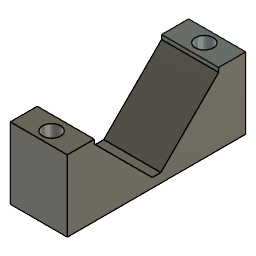
Main Bottom Side Assembly (Autodesk Fusion 360 archive; units mm, degrees)
design "Drive Motor Mount Base Top Half"
Autodesk Fusion 360 part; units mm, degrees
(part 1 of 3)
ref_plane "WorkPlane1" through (0, 0, 0) normal (1, 0, 0) x (0, 1, 0)
sketch "Sketch3" plane through (0, 0, 0) normal (1, 0, 0) x (0, 1, 0)
  line L0 (-15.875, 0) -> (15.875, 0)
  line L1 (15.875, 0) -> (15.875, -12.7)
  line L2 (15.875, -12.7) -> (-15.875, -12.7)
  line L3 (-15.875, -12.7) -> (-15.875, 0)
  line L4 (-11.049, 0) -> (-11.049, -0.762)
  line L5 (-11.049, -0.762) -> (-0.762, -11.049)
  line L6 (-0.762, -11.049) -> (0.762, -11.049)
  line L7 (0.762, -11.049) -> (11.049, -0.762)
  line L8 (11.049, -0.762) -> (11.049, 0)
  dimension "d12" = 31.75
  dimension "d13" = 12.7
  dimension "d14" = 0.762
  dimension "d15" = 4.826
  dimension "d16" = 4.826
  dimension "d17" = 1.524
  constraint horizontal L0
  constraint vertical L1
  constraint horizontal L2
  constraint vertical L3
  constraint coincident L0 L4.start
  constraint perpendicular L0 L4
  constraint horizontal L6
  constraint coincident L0 L8.end
  constraint perpendicular L0 L8
  constraint equal L4 L8
  constraint equal L5 L7
  constraint perpendicular L5 L7
  constraint midpoint origin L0
  measures "d12" distance of L1.end L2.end
  measures "d13" distance of L0.start L2.end
  measures "d14" distance of L4.start L4.end
  measures "d15" distance of L0.start L4.start
  measures "d16" distance of L0.end L8.end
  measures "d17" distance of L5.end L6.end
extrude "Extrude2" add sketch "Sketch3" along normal blind 10.16 contours L0 L1 L2 L3 L4 L5 L6 L7 L8
sketch "Sketch4" plane through (0, 0, 0) normal (0, 0, 1) x (-1, 0, 0)
  line L0 (0, -15.875) -> (0, -11.049)
  line L1 (0, -11.049) -> (-10.16, -11.049)
  line L2 (-10.16, -11.049) -> (-10.16, -15.875)
  line L3 (-10.16, -15.875) -> (0, -15.875)
sketch "Sketch5" plane through (10.16, 0, 0) normal (1, 0, 0) x (0, -1, 0)
  line L0 (-11.049, 0.762) -> (-0.762, 11.049)
  line L1 (-0.762, 11.049) -> (0.762, 11.049)
  line L2 (0.762, 11.049) -> (11.049, 0.762)
  line L3 (11.049, 0.762) -> (11.049, 0)
  line L4 (11.049, 0) -> (15.875, 0)
  line L5 (15.875, 0) -> (15.875, 12.7)
  line L6 (15.875, 12.7) -> (-15.875, 12.7)
  line L7 (-15.875, 12.7) -> (-15.875, 0)
  line L8 (-15.875, 0) -> (-11.049, 0)
  line L9 (-11.049, 0) -> (-11.049, 0.762)
  arc A0 (-12.7, 0) -> (12.7, 0) centre (0, 0) ccw
  line L10 (-11.6397, -5.08) -> (15.875, -5.08)
  line L11 (11.6397, -5.08) -> (-15.875, -5.08)
  line L12 (-15.875, 0) -> (-11.049, 0)
  dimension "d21" = 5.08
  dimension "d22" = 5.08
  dimension "d34" = 12.7
  constraint coincident A0.centre origin
  constraint coincident L8 A0.end
  constraint coincident L4 A0.start
  constraint coincident A0 L10.start
  constraint coincident L5 L10.end
  constraint perpendicular L5 L10
  constraint coincident A0 L11.start
  constraint coincident L7 L11.end
  constraint perpendicular L7 L11
  measures "d21" distance of L4 L10
  measures "d22" distance of L11 L12
  measures "d34" radius of A0
extrude "Extrude3" add sketch "Sketch5" against normal up to surface (10.16 mm away) contours L0 L1 L2 L3 L4 L5 L6 L7 L8 L9 L12
sketch "Sketch7" plane through (0, 0, 0) normal (0, 0, 1) x (-1, 0, 0)
  line L0 (0, 11.049) -> (0, 15.875)
  line L1 (0, 15.875) -> (-10.16, 15.875)
  line L2 (-10.16, 15.875) -> (-10.16, 11.049)
  line L3 (-10.16, 11.049) -> (0, 11.049)
  circle A0 centre (-5.08, 13.589) radius 1.6
  circle A1 centre (-5.08, -13.589) radius 1.6
  line L4 (-10.16, -15.875) -> (0, -15.875)
  line L5 (-10.16, -11.049) -> (-10.16, -15.875)
  dimension "d35" = 3.2
  dimension "d36" = 3.2
  dimension "d37" = 2.286
  dimension "d38" = 2.286
  dimension "d39" = 5.08
  dimension "d40" = 5.08
  measures "d35" diameter of A1
  measures "d36" diameter of A0
  measures "d37" distance of A1.centre L4
  measures "d38" distance of L1 A0.centre
  measures "d39" distance of L2 A0.centre
  measures "d40" distance of A1.centre L5
extrude "Extrude5" cut sketch "Sketch7" against normal blind 12.7 contours A0 | A1

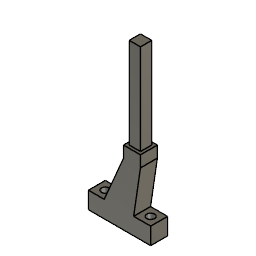
design "Rear Frame Mount"
Autodesk Fusion 360 part; units mm, degrees
sketch "Sketch1" plane through (0, 0, 0) normal (0, 1, 0) x (1, 0, 0)
  line L0 (0, 0) -> (-25.4, 0)
  line L1 (-25.4, 0) -> (-25.4, -9.525)
  line L2 (-25.4, -9.525) -> (0, -9.525)
  line L3 (0, -9.525) -> (0, 0)
  line L4 (-25.4, 0) -> (-34.925, 0)
  line L5 (-34.925, 0) -> (-34.925, -9.525)
  line L6 (-34.925, -9.525) -> (-25.4, -9.525)
  line L7 (-25.4, -9.525) -> (-25.4, 0)
  line L8 (-26.035, -9.525) -> (-15.24, -34.925)
  line L9 (-15.24, -34.925) -> (-5.715, -34.925)
  line L10 (-5.715, -34.925) -> (-9.525, -9.525)
  line L11 (-15.24, -34.925) -> (-5.715, -34.925)
  line L12 (-5.715, -34.925) -> (-5.715, -41.275)
  line L13 (-5.715, -41.275) -> (-15.24, -41.275)
  line L14 (-15.24, -41.275) -> (-15.24, -34.925)
  dimension "d3" = 34.925
  dimension "d4" = 9.525
  dimension "d5" = 25.4
  dimension "d6" = 9.525
  dimension "d7" = 9.525
  dimension "d26" = 6.35
  dimension "d27" = 25.4
  dimension "d28" = 9.525
  dimension "d30" = 16.51
  dimension "d31" = 3.81
  dimension "d32" = 9.525
  constraint horizontal L0
  constraint vertical L1
  constraint horizontal L2
  constraint vertical L3
  constraint coincident L0.start L3.end
  constraint horizontal L4
  constraint vertical L5
  constraint horizontal L6
  constraint vertical L7
  constraint coincident L2 L8.start
  constraint perpendicular L1 L9
  constraint coincident L2 L10.end
  constraint horizontal L11
  constraint vertical L12
  constraint horizontal L13
  constraint vertical L14
  constraint horizontal L0.end L4.end
  measures "d3" distance of L3 L5
  measures "d4" distance of L0.end L4.end
  measures "d5" distance of L0.start L0.end
  measures "d6" distance of L4.end L5.end
  measures "d7" distance of L0.start L2.end
  measures "d26" distance of L9.end L12.end
  measures "d27" distance of L2 L9
  measures "d28" distance of L12 L14
  measures "d30" distance of L8.start L10.end
  measures "d31" horizontal distance of L10.end L9.end
  measures "d32" distance of L2.end L10.end
extrude "Extrude1" add sketch "Sketch1" along normal blind 9.525
sketch "Sketch2" plane through (0, 0, 9.525) normal (0, 0, 1) x (-1, 0, 0)
  line L0 (34.925, 0) -> (26.035, 0)
  line L1 (0, 0) -> (0, -9.525)
  line L2 (26.035, -9.525) -> (34.925, -9.525)
  line L3 (34.925, -9.525) -> (34.925, 0)
  circle A0 centre (30.1625, -4.7625) radius 2.1971
  circle A1 centre (4.7625, -4.7625) radius 2.1971
  line L4 (26.035, 0) -> (26.035, -9.525)
  line L5 (9.525, 0) -> (0, 0)
  line L6 (0, -9.525) -> (9.525, -9.525)
  line L7 (9.525, -9.525) -> (9.525, 0)
  dimension "d10" = 4.3942
  dimension "d11" = 4.3942
  dimension "d12" = 4.7625
  dimension "d13" = 4.7625
  dimension "d14" = 25.4
  dimension "d15" = 4.7625
  measures "d10" diameter of A0
  measures "d11" diameter of A1
  measures "d12" distance of L2 A0.centre
  measures "d13" distance of L2 A1.centre
  measures "d14" distance of A0.centre A1.centre
  measures "d15" distance of L3 A0.centre
extrude "Extrude2" cut sketch "Sketch2" against normal blind 9.525 contours A0 | A1
sketch "Sketch5" plane through (0, 0, 41.275) normal (0, 0, 1) x (-1, 0, 0)
  line L0 (15.24, 0) -> (5.715, 0)
  line L1 (5.715, 0) -> (5.715, -9.525)
  line L2 (5.715, -9.525) -> (15.24, -9.525)
  line L3 (15.24, -9.525) -> (15.24, 0)
  line L4 (13.6525, -7.9375) -> (7.3025, -7.9375)
  line L5 (7.3025, -7.9375) -> (7.3025, -1.5875)
  line L6 (7.3025, -1.5875) -> (13.6525, -1.5875)
  line L7 (13.6525, -1.5875) -> (13.6525, -7.9375)
  dimension "d33" = 6.35
  dimension "d34" = 6.35
  dimension "d35" = 1.5875
  dimension "d36" = 1.5875
  constraint horizontal L4
  constraint vertical L5
  constraint horizontal L6
  constraint vertical L7
  measures "d33" distance of L4.end L5.end
  measures "d34" distance of L4.start L4.end
  measures "d35" distance of L2 L4
  measures "d36" distance of L1 L5
extrude "Extrude5" add sketch "Sketch5" along normal blind 50.8 contours L4 L5 L6 L7
equation "d12 = ( 0.375 / 2 ) * 1 in"
equation "d13 = ( 3 / 16 ) * 1 in"
equation "d15 = ( 3 / 16 ) * 1 in"
equation "d28 = ( 3 / 8 ) * 1 in"
equation "d35 = ( 1 / 16 ) * 1 in"
equation "d36 = ( 1 / 16 ) * 1 in"
equation "d29 = ( 3 / 8 ) * 1 in"

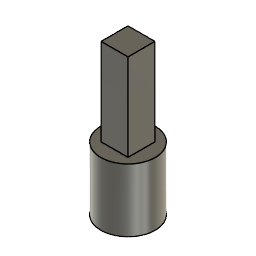
design "Small bevel coupling"
Autodesk Fusion 360 part; units mm, degrees
sketch "Sketch1" plane through (0, 0, 0) normal (0, 0, 1) x (1, 0, 0)
  line L0 (-1.397, 1.6995) -> (1.397, 1.6995)
  arc A0 (-1.397, 1.6995) -> (1.397, 1.6995) centre (0, 0) ccw
  circle A1 centre (0, 0) radius 3.175
  dimension "d1" = 4.4
  dimension "d2" = 2.794
  dimension "d8" = 3.175
  constraint coincident A0.centre A1.centre
  constraint horizontal L0
  constraint concentric A0 A1
  measures "d1" diameter of A0
  measures "d2" distance of L0.start L0.end
  measures "d8" radius of A1
extrude "Extrude1" add sketch "Sketch1" along normal blind 6.35
sketch "Sketch4" plane through (0, 0, 6.35) normal (0, 0, 1) x (-1, 0, 0)
  arc A0 (1.397, -1.6995) -> (-1.397, -1.6995) centre (0, 0) ccw
  line L0 (1.397, -1.6995) -> (-1.397, -1.6995)
  circle A1 centre (0, 0) radius 3.175
  circle A2 centre (0, 0) radius 3.175
  dimension "d9" = 6.35
  constraint coincident A0.centre A1.centre
  measures "d9" diameter of A2
extrude "Extrude2" add sketch "Sketch4" along normal blind 1.016 contours A0 L0 | A1 A2
sketch "Sketch5" plane through (0, 0, 7.366) normal (0, 0, 1) x (-1, 0, 0)
  circle A0 centre (0, 0) radius 3.175
  line L0 (-1.5748, -1.5748) -> (1.5748, -1.5748)
  line L1 (1.5748, -1.5748) -> (1.5748, 1.5748)
  line L2 (1.5748, 1.5748) -> (-1.5748, 1.5748)
  line L3 (-1.5748, 1.5748) -> (-1.5748, -1.5748)
  line L4 (-1.5748, -1.5748) -> (1.5748, 1.5748) construction
  line L5 (1.5748, -1.5748) -> (-1.5748, 1.5748) construction
  dimension "d12" = 3.1496
  dimension "d13" = 3.1496
  constraint horizontal L0
  constraint perpendicular L0 L1
  constraint parallel L0 L2
  constraint parallel L1 L3
  constraint coincident L4 A0.centre
  constraint coincident L5 A0.centre
  constraint coincident A0.centre origin
  measures "d12" distance of L0.end L1.end
  measures "d13" distance of L0.start L0.end
extrude "Extrude3" add sketch "Sketch5" along normal blind 10.16 contours L0 L1 L2 L3

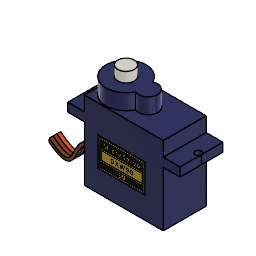
design "Servo-Motor"
Autodesk Fusion 360 part; units mm, degrees
sketch "Sketch1" plane through (0, 0, 0) normal (0, -1, 0) x (1, 0, 0)
  line L0 (-16.065, 4.55) -> (-11.275, 4.55)
  line L1 (-11.275, 4.55) -> (-11.275, -11.2)
  line L2 (-11.275, -11.2) -> (11.275, -11.2)
  line L3 (11.275, -11.2) -> (11.275, 4.55)
  line L4 (11.275, 4.55) -> (16.065, 4.55)
  line L5 (16.065, 4.55) -> (16.065, 7.05)
  line L6 (16.065, 7.05) -> (11.275, 7.05)
  line L7 (11.275, 7.05) -> (11.275, 11.2)
  line L8 (11.275, 11.2) -> (-11.275, 11.2)
  line L9 (-11.275, 11.2) -> (-11.275, 7.05)
  line L10 (-11.275, 7.05) -> (-16.065, 7.05)
  line L11 (-16.065, 7.05) -> (-16.065, 4.55)
  line L12 (-11.275, 11.2) -> (11.275, 11.2)
  line L13 (11.275, 11.2) -> (11.275, 7.05)
  line L14 (11.275, 7.05) -> (16.065, 7.05)
  line L15 (16.065, 4.55) -> (16.065, 7.05)
  line L16 (16.065, 4.55) -> (11.275, 4.55)
  line L17 (11.275, 4.55) -> (11.275, -11.2)
  line L18 (11.275, -11.2) -> (-11.275, -11.2)
  line L19 (-11.275, -11.2) -> (-11.275, 4.55)
  line L20 (-16.065, 4.55) -> (-16.065, 7.05)
  line L21 (-16.065, 7.05) -> (-11.275, 7.05)
  line L22 (-11.275, 7.05) -> (-11.275, 11.2)
  line L23 (-11.275, 4.55) -> (-16.065, 4.55)
  constraint coincident L8.end L9.start
  constraint coincident L7.end L8.start
  constraint coincident L6.end L7.start
  constraint coincident L5.end L6.start
  constraint coincident L4.end L5.start
  constraint coincident L3.end L4.start
  constraint coincident L2.end L3.start
  constraint coincident L1.end L2.start
  constraint coincident L0.end L1.start
  constraint coincident L0.start L11.end
  constraint coincident L10.end L11.start
  constraint coincident L9.end L10.start
extrude "Extrude1" add sketch "Sketch1" along normal blind 12.3 makes body 1
move_body "Move1" bodies 1 to x (1, 0, 0) y (0, 1, 0) z (0, 0, 1) at (0, 6.15, 0)
sketch "Sketch2" plane through (0, 0, 11.2) normal (0, 0, 1) x (-1, 0, 0)
  line L0 (-11.275, -6.15) -> (11.275, -6.15)
  line L1 (11.275, -6.15) -> (11.275, 6.15)
  line L2 (11.275, 6.15) -> (-11.275, 6.15)
  line L3 (-11.275, 6.15) -> (-11.275, -6.15)
  line L4 (16.065, -6.15) -> (16.065, 6.15)
  line L5 (-16.065, -6.15) -> (-16.065, 6.15)
  line L6 (16.065, 0) -> (-16.065, 0) construction
  line L7 (0, 6.15) -> (0, -6) construction
  circle A0 centre (15.19, 0) radius 0.875
  circle A1 centre (-15.19, 0) radius 0.875
  line L8 (-11.275, 0) -> (-3.525, 0) construction
  line L9 (-3.525, 3.3214) -> (-3.525, -3) construction
  arc A2 (0.3298, 2.4642) -> (0.3298, -2.4642) centre (-0.81, 0) ccw
  arc A3 (0.3298, -2.4642) -> (0.3298, 2.4642) centre (5.525, 0) ccw
  dimension "d10" = 1.75
  dimension "d11" = 11.5
  dimension "d12" = 7.75
  dimension "d13" = 5.43
  constraint midpoint L5 L6.end
  constraint midpoint L2 L7.start
  constraint perpendicular L6 L7
  constraint coincident L6 A0.centre
  constraint tangent L4 A0
  constraint symmetric L7 A0 A1
  constraint coincident L6 A3.centre
  constraint tangent L1 A3
  constraint midpoint L3 L8.start
  constraint horizontal L8
  constraint coincident L6 A2.centre
  constraint perpendicular L6 L9
  constraint tangent L9 A2
  measures "d10" diameter of A0
  measures "d11" diameter of A3
  measures "d12" distance of L8.start L8.end
  measures "d13" diameter of A2
extrude "Extrude2" add sketch "Sketch2" along normal blind 4.45 contours A2 A3 bodies 1
copy_body "Body->Comp1" bodies 1 removing the originals makes body 2 in component "Blue Body"
sketch "Sketch1 (2)" plane through (0, 0, 15.65) normal (0, 0, 1) x (-1, 0, 0) in component "Gears"
  arc A0 (0.3298, -2.4642) -> (0.3298, 2.4642) centre (5.525, 0) ccw
  arc A1 (0.3298, 2.4642) -> (0.3298, -2.4642) centre (-0.81, 0) ccw
  circle A2 centre (5.525, 0) radius 2.35
  dimension "d16" = 4.7
  constraint concentric A0 A2
  measures "d16" diameter of A2
extrude "Extrude1'" add sketch "Sketch1 (2)" along normal blind 2.88 separate body contours A2 makes body 3 in component "Gears"
extrude "Extrude1''" cut sketch "Sketch2" against normal blind 2.5 from surface at -4.15 contours A0 | A1 bodies 2 in component "Blue Body"
sketch "Sketch1 (3)" plane through (-11.275, 0, 0) normal (-1, 0, 0) x (0, -1, 0) in component "Wires"
  line L0 (-6.15, 4.55) -> (-6.15, -11.2)
  line L1 (-6.15, -11.2) -> (6.15, -11.2)
  line L2 (6.15, -11.2) -> (6.15, 4.55)
  line L3 (6.15, 4.55) -> (-6.15, 4.55)
  line L4 (0, -11.2) -> (0, -6.45) construction
  line L5 (1.65, -6.45) -> (1.65, -5.45)
  line L6 (1.65, -5.45) -> (-1.65, -5.45)
  line L7 (-1.65, -5.45) -> (-1.65, -6.45)
  line L8 (-1.65, -6.45) -> (1.65, -6.45)
  line L9 (-1.65, -5.45) -> (-0.55, -5.45)
  line L10 (-0.55, -5.45) -> (0.55, -5.45)
  line L11 (0.55, -5.45) -> (0.55, -6.45)
  line L12 (-0.55, -5.45) -> (-0.55, -6.45)
  dimension "d35" = 1.65
  dimension "d36" = 1
  dimension "d37" = 3.3
  dimension "d38" = 1.1
  dimension "d39" = 1.1
  constraint midpoint L1 L4.start
  constraint vertical L4
  constraint vertical L5
  constraint horizontal L6
  constraint vertical L7
  constraint perpendicular L5 L8
  constraint horizontal L9
  constraint horizontal L10
  constraint coincident L8 L11.end
  constraint perpendicular L8 L11
  constraint coincident L8 L12.end
  constraint perpendicular L8 L12
  measures "d35" distance of L4.end L7.end
  measures "d36" distance of L7.end L6.end
  measures "d37" distance of L7.end L5.start
  measures "d38" distance of L6.end L9.end
  measures "d39" distance of L9.end L10.end
sketch "Sketch2 (2)" plane through (0, 0, 0) normal (0, 1, 0) x (1, 0, 0) in component "Wires"
  spline S0 degree 5 poles (-11.275, 6.45) (-11.5653, 6.2839) (-12.1299, 5.9875) (-12.9291, 5.6496) (-13.8988, 5.4144) (-14.9497, 5.4819) (-15.8436, 5.9016) (-16.5945, 6.6425) (-17.233, 7.6365) (-17.8087, 8.7735) (-18.38, 9.9234) (-19.0073, 10.9519) (-19.7452, 11.7374) (-20.6338, 12.1904) (-21.694, 12.2646) (-22.9344, 11.9406) (-24.0716, 11.3613) (-25.0048, 10.7492) (-25.6623, 10.2628) (-26, 10) knots 0 0 0 0 0 0 0.066667 0.133333 0.2 0.266667 0.333333 0.4 0.466667 0.533333 0.6 0.666667 0.733333 0.8 0.866667 0.933333 1 1 1 1 1 1
  point P0 (-16.3437, 6.45)
  point P1 (-19.5666, 11.4764)
  point P2 (-11.275, 6.45)
  constraint coincident P2 S0.start
sweep "Sweep1" add profiles "Sketch1 (3)" path "Sketch2 (2)" along S0 section 1 contours L6 L7 L8 L9 L12 separate body makes body 4 in component "Wires"
sweep "Sweep2" add profiles "Sketch1 (3)" path "Sketch2 (2)" along S0 section 1 contours L6 L8 L10 L11 L12 separate body makes body 5 in component "Wires"
sweep "Sweep3" add profiles "Sketch1 (3)" path "Sketch2 (2)" along S0 section 1 contours L5 L6 L8 L11 separate body makes body 6 in component "Wires"
component "Gears" placed x (1, 0, 0) y (0, 1, 0) z (0, 0, 1) at (0, 0, 0)
component "Blue Body" placed x (1, 0, 0) y (0, 1, 0) z (0, 0, 1) at (0, 0, 0)
component "Wires" placed x (1, 0, 0) y (0, 1, 0) z (0, 0, 1) at (0, 0, 0)
equation "d35 = ( 3.3 / 2 ) * 1 mm"
equation "d38 = ( 3.3 / 3 ) * 1 mm"
equation "d39 = ( 3.3 / 3 ) * 1 mm"
named bodies: "Orange", "Red", "Brown"

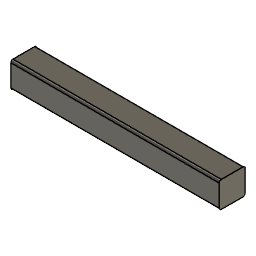
design "Front steering axle"
Autodesk Fusion 360 part; units mm, degrees
sketch "Sketch1" plane through (0, 0, 0) normal (1, 0, 0) x (0, 1, 0)
  line L0 (0, 3.175) -> (3.175, 3.175)
  line L1 (3.175, 3.175) -> (3.175, 0)
  line L2 (3.175, 0) -> (0, 0)
  line L3 (0, 0) -> (0, 3.175)
  dimension "d1" = 3.175
  dimension "d2" = 3.175
  constraint horizontal L0
  constraint vertical L1
  constraint horizontal L2
  constraint vertical L3
  constraint coincident L2.end L3.start
  measures "d1" distance of L0.end L1.end
  measures "d2" distance of L0.start L0.end
extrude "Extrude1" add sketch "Sketch1" along normal blind 25.4
fillet "Fillet1" radius 0.254 4 edges at (12.7, 0, 3.175) (12.7, 3.175, 3.175) (12.7, 0, 0) (12.7, 3.175, 0)

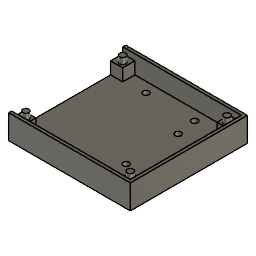
design "Controller Mounting"
Autodesk Fusion 360 part; units mm, degrees
sketch "Sketch1" plane through (0, 0, 0) normal (0, 0, 1) x (1, 0, 0)
  line L0 (0, 0) -> (65.175, 0)
  line L1 (65.175, 0) -> (65.175, 61.175)
  line L2 (65.175, 61.175) -> (0, 61.175)
  line L3 (0, 61.175) -> (0, 0)
  dimension "d1" = 61.175
  dimension "d2" = 65.175
  constraint horizontal L0
  constraint vertical L1
  constraint horizontal L2
  constraint vertical L3
  constraint coincident L0.start L3.end
  measures "d1" distance of L0.start L2.end
  measures "d2" distance of L0.start L0.end
extrude "Extrude1" add sketch "Sketch1" along normal blind 12.7
sketch "Sketch4" plane through (0, 0, 12.7) normal (0, 0, 1) x (-1, 0, 0)
  line L0 (0, -61.175) -> (0, 0)
  line L1 (0, 0) -> (-65.175, 0)
  line L2 (-65.175, 0) -> (-65.175, -61.175)
  line L3 (-65.175, -61.175) -> (0, -61.175)
  line L4 (-1.5875, -1.5875) -> (-63.5875, -1.5875)
  line L5 (-63.5875, -1.5875) -> (-63.5875, -59.5875)
  line L6 (-63.5875, -59.5875) -> (-1.5875, -59.5875)
  line L7 (-1.5875, -59.5875) -> (-1.5875, -1.5875)
  dimension "d10" = 1.5875
  dimension "d11" = 1.5875
  dimension "d12" = 1.5875
  dimension "d13" = 1.5875
  constraint horizontal L4
  constraint vertical L5
  constraint horizontal L6
  constraint vertical L7
  measures "d10" distance of L0 L7
  measures "d11" distance of L3 L6
  measures "d12" distance of L1 L4
  measures "d13" distance of L2 L5
extrude "Extrude2" cut sketch "Sketch4" against normal blind 9.525 contours L4 L5 L6 L7
sketch "Sketch5" plane through (0, 0, 0) normal (-1, 0, 0) x (0, -1, 0)
  line L0 (-61.175, 0) -> (0, 0)
  line L1 (0, 0) -> (0, 12.7)
  line L2 (0, 12.7) -> (-61.175, 12.7)
  line L3 (-61.175, 12.7) -> (-61.175, 0)
  line L4 (-53.2375, 12.7) -> (-7.9375, 12.7)
  line L5 (-7.9375, 12.7) -> (-7.9375, 0)
  line L6 (-53.2375, 0) -> (-53.2375, 12.7)
  line L7 (-53.2375, 3.175) -> (-59.5875, 3.175)
  line L8 (-59.5875, 3.175) -> (-59.5875, 12.7)
  line L9 (-59.5875, 12.7) -> (-53.2375, 12.7)
  line L10 (-53.2375, 12.7) -> (-53.2375, 3.175)
  line L11 (-7.9375, 3.175) -> (-1.5875, 3.175)
  line L12 (-1.5875, 3.175) -> (-1.5875, 12.7)
  line L13 (-1.5875, 12.7) -> (-7.9375, 12.7)
  line L14 (-7.9375, 12.7) -> (-7.9375, 3.175)
  line L15 (-53.2375, 3.175) -> (-7.9375, 3.175)
  dimension "d76" = 1.5875
  dimension "d77" = 3.175
  dimension "d78" = 3.175
  dimension "d79" = 1.5875
  dimension "d80" = 6.35
  dimension "d81" = 6.35
  constraint horizontal L4
  constraint vertical L5
  constraint vertical L6
  constraint coincident L2 L4.start
  constraint horizontal L5.end L6.start
  constraint horizontal L0.end L6.start
  constraint horizontal L7
  constraint vertical L8
  constraint horizontal L9
  constraint vertical L10
  constraint coincident L2 L8.end
  constraint coincident L6 L7.start
  constraint horizontal L11
  constraint vertical L12
  constraint horizontal L13
  constraint vertical L14
  constraint coincident L2 L12.end
  constraint coincident L5 L11.start
  measures "d76" distance of L3 L8
  measures "d77" distance of L0 L7
  measures "d78" distance of L0 L11
  measures "d79" distance of L1 L12
  measures "d80" distance of L8 L10
  measures "d81" distance of L12 L14
extrude "Extrude3" cut sketch "Sketch5" against normal blind 1.5875
sketch "Sketch6" plane through (0, 0, 3.175) normal (0, 0, 1) x (-1, 0, 0)
  circle A0 centre (-59.8375, -5.3375) radius 1.65
  circle A1 centre (-5.3375, -5.3375) radius 1.65
  circle A2 centre (-59.8375, -55.8375) radius 1.65
  circle A3 centre (-5.3375, -55.8375) radius 1.65
  line L0 (-63.5875, -1.5875) -> (-57.2375, -1.5875)
  line L1 (-57.2375, -1.5875) -> (-57.2375, -7.9375)
  line L2 (-57.2375, -7.9375) -> (-63.5875, -7.9375)
  line L3 (-63.5875, -7.9375) -> (-63.5875, -1.5875)
  line L4 (-63.5875, -59.5875) -> (-57.2375, -59.5875)
  line L5 (-57.2375, -59.5875) -> (-57.2375, -53.2375)
  line L6 (-57.2375, -53.2375) -> (-63.5875, -53.2375)
  line L7 (-63.5875, -53.2375) -> (-63.5875, -59.5875)
  line L8 (-1.5875, -59.5875) -> (-7.9375, -59.5875)
  line L9 (-7.9375, -59.5875) -> (-7.9375, -53.2375)
  line L10 (-7.9375, -53.2375) -> (-1.5875, -53.2375)
  line L11 (-1.5875, -53.2375) -> (-1.5875, -59.5875)
  line L12 (-1.5875, -1.5875) -> (-7.9375, -1.5875)
  line L13 (-7.9375, -1.5875) -> (-7.9375, -7.9375)
  line L14 (-7.9375, -7.9375) -> (-1.5875, -7.9375)
  line L15 (-1.5875, -7.9375) -> (-1.5875, -1.5875)
  line L16 (-65.175, 0) -> (-65.175, -61.175)
  line L17 (-65.175, -61.175) -> (0, -61.175)
  line L18 (-1.5875, -1.5875) -> (-63.5875, -1.5875)
  line L19 (-63.5875, -1.5875) -> (-63.5875, -59.5875)
  line L20 (-63.5875, -59.5875) -> (-1.5875, -59.5875)
  line L21 (-1.5875, -59.5875) -> (-1.5875, -1.5875)
  dimension "d82" = 3.3
  dimension "d83" = 50.5
  dimension "d84" = 50.5
  dimension "d85" = 54.5
  dimension "d86" = 3.3
  dimension "d87" = 3.3
  dimension "d88" = 5.3375
  dimension "d89" = 5.3375
  dimension "d90" = 6.35
  dimension "d91" = 6.35
  dimension "d92" = 6.35
  dimension "d93" = 6.35
  dimension "d94" = 6.35
  dimension "d95" = 6.35
  dimension "d96" = 6.35
  dimension "d97" = 6.35
  dimension "d98" = 1.5875
  dimension "d100" = 1.5875
  dimension "d101" = 1.5875
  dimension "d102" = 1.5875
  constraint horizontal A0.centre A1.centre
  constraint horizontal A2.centre A3.centre
  constraint vertical A1.centre A3.centre
  constraint equal A0 A1
  constraint horizontal L0
  constraint vertical L1
  constraint horizontal L2
  constraint vertical L3
  constraint horizontal L4
  constraint vertical L5
  constraint horizontal L6
  constraint vertical L7
  constraint horizontal L8
  constraint vertical L9
  constraint horizontal L10
  constraint vertical L11
  constraint horizontal L12
  constraint vertical L13
  constraint horizontal L14
  constraint vertical L15
  constraint horizontal L1.end L13.end
  constraint vertical L9.end L13.end
  constraint horizontal L5.end L9.end
  constraint vertical L1.end L5.end
  measures "d82" diameter of A0
  measures "d83" distance of A0.centre A2.centre
  measures "d84" vertical distance of A1.centre A3.centre
  measures "d85" distance of A0.centre A1.centre
  measures "d86" diameter of A2
  measures "d87" diameter of A3
  measures "d88" vertical distance of origin A0.centre
  measures "d89" horizontal distance of origin A1.centre
  measures "d90" distance of L12.end L13.end
  measures "d91" distance of L13.end L14.end
  measures "d92" distance of L9.end L10.end
  measures "d93" distance of L8.end L9.end
  measures "d94" distance of L4.end L5.end
  measures "d95" distance of L5.end L6.end
  measures "d96" distance of L1.end L2.end
  measures "d97" distance of L0.end L1.end
  measures "d98" distance of origin L12
  measures "d100" distance of origin L15
  measures "d101" distance of L3 L16
  measures "d102" distance of L4 L17
extrude "Extrude4" add sketch "Sketch6" along normal blind 6.35 contours A0 | A1 | A2 | A3 | L0 L1 L2 L3 L18 L19 | L12 L13 L14 L15 L18 L21 | L4 L5 L6 L7 L19 L20 | L8 L9 L10 L11 L20 L21
extrude "Extrude8" add sketch "Sketch6" along normal blind 9.525 contours A0 | A1 | A2 | A3
sketch "Sketch7" plane through (0, 0, 3.175) normal (0, 0, 1) x (-1, 0, 0)
  line L0 (-7.9375, -1.5875) -> (-57.2375, -1.5875)
  circle A0 centre (-45.9695, -16.9985) radius 1.6
  circle A1 centre (-45.9695, -44.1765) radius 1.6
  line L1 (-1.5875, 0) -> (-65.175, 0)
  line L2 (-45.9695, -16.9985) -> (-45.9695, -44.1765)
  line L3 (-46.0504, 0) -> (-45.8887, -61.175)
  line L4 (-65.175, -61.175) -> (-1.5875, -61.175)
  line L5 (-57.2375, -59.5875) -> (-7.9375, -59.5875)
  line L6 (-63.5875, -7.9375) -> (-63.5875, -53.2375)
  line L7 (-63.5875, -53.2375) -> (-57.2375, -53.2375)
  line L8 (-57.2375, -53.2375) -> (-57.2375, -59.5875)
  line L9 (-7.9375, -59.5875) -> (-7.9375, -53.2375)
  line L10 (-7.9375, -53.2375) -> (-1.5875, -53.2375)
  line L11 (-1.5875, -53.2375) -> (-1.5875, -7.9375)
  line L12 (-1.5875, -7.9375) -> (-7.9375, -7.9375)
  line L13 (-7.9375, -7.9375) -> (-7.9375, -1.5875)
  line L14 (-57.2375, -1.5875) -> (-57.2375, -7.9375)
  line L15 (-57.2375, -7.9375) -> (-63.5875, -7.9375)
  dimension "d41" = 3.2
  dimension "d42" = 3.2
  dimension "d43" = 27.178
  dimension "d57" = 46.0502
  constraint vertical A0.centre A1.centre
  constraint coincident A0.centre L2.start
  constraint coincident A1.centre L2.end
  constraint coincident L1 L3.start
  constraint midpoint L2 L3
  constraint coincident L3.end L4
  measures "d41" diameter of A1
  measures "d42" diameter of A0
  measures "d43" distance of A0.centre A1.centre
  measures "d57" distance of origin L3
extrude "Extrude5" cut sketch "Sketch7" against normal blind 3.175 contours A0 L3 | A0 L3 | A1 L3 | A1 L3
sketch "Sketch9" plane through (0, 0, 0) normal (0, 0, -1) x (1, 0, 0)
  line L0 (1.5875, -61.175) -> (65.175, -61.175)
  line L1 (65.175, -61.175) -> (65.175, 0)
  line L2 (65.175, 0) -> (1.5875, 0)
  circle A0 centre (19.0373, -54.4) radius 1.6
  circle A1 centre (44.4373, -54.4) radius 1.6
  circle A2 centre (19.0373, -6.775) radius 1.6
  circle A3 centre (44.4373, -6.775) radius 1.6
  circle A4 centre (45.9695, -16.9985) radius 1.6
  circle A5 centre (45.9695, -44.1765) radius 1.6
  line L3 (44.4373, -6.775) -> (44.4373, 0)
  line L4 (44.4373, -54.4) -> (44.4373, -61.175)
  line L5 (1.5875, 0) -> (1.5875, -61.175)
  dimension "d60" = 3.2
  dimension "d61" = 3.2
  dimension "d75" = 25.4
  dimension "d105" = 47.625
  dimension "d106" = 47.625
  constraint vertical A0.centre A2.centre
  constraint vertical A1.centre A3.centre
  constraint equal A0 A2
  constraint equal A0 A3
  constraint horizontal A2.centre A3.centre
  constraint coincident A3.centre L3.start
  constraint coincident L2 L3.end
  constraint perpendicular L2 L3
  constraint coincident A1.centre L4.start
  constraint coincident L0 L4.end
  constraint perpendicular L0 L4
  constraint equal L3 L4
  measures "d60" diameter of A0
  measures "d61" diameter of A1
  measures "d75" distance of A0.centre A1.centre
  measures "d105" distance of A1.centre A3.centre
  measures "d106" distance of A0.centre A2.centre
extrude "Extrude7" cut sketch "Sketch9" along normal blind -20.32 and the other way blind 0 contours A0 | A1 | A2 | A3
equation "d1 = 58 mm + 0.125 in"
equation "d2 = 62 mm + 0.125 in"
equation "d10 = ( 1 / 16 ) * 1 in"
equation "d11 = ( 1 / 16 ) * 1 in"
equation "d12 = ( 1 / 16 ) * 1 in"
equation "d13 = ( 1 / 16 ) * 1 in"
equation "d14 = -0.5 in + 0.125 in"
equation "d20 = ( -1 / 16 ) * 1 in"
equation "d57 = 1.8 in + 0.388 in - 0.375 in"
equation "d76 = ( 1 / 16 ) * 1 in"
equation "d79 = ( 1 / 16 ) * 1 in"
equation "d88 = ( 1 / 16 ) * 1 in + 3.75 mm"
equation "d89 = ( 1 / 16 ) * 1 in + 3.75 mm"
equation "d98 = ( 1 / 16 ) * 1 in"
equation "d100 = ( 1 / 16 ) * 1 in"
equation "d101 = ( 1 / 16 ) * 1 in"
equation "d102 = ( 1 / 16 ) * 1 in"
equation "d58 = 0.5 in - 0.052 in - 0.0865 in + 0.388 in"
equation "d71 = 0.101 in + ( 0.173 / 2 ) * 1 in"
equation "d72 = 0.101 in + ( 0.173 / 2 ) * 1 in"

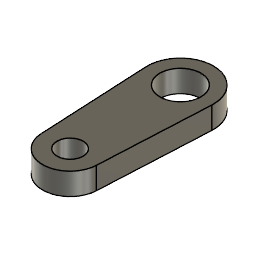
design "Single Arm"
Autodesk Fusion 360 part; units mm, degrees
sketch "Sketch1" plane through (0, 0, 0) normal (0, 0, 1) x (1, 0, 0)
  circle A0 centre (0, 0) radius 2.3622
  circle A1 centre (0, 0) radius 3.81
  circle A2 centre (0, -12.7) radius 3.175
  line L0 (-3.8052, -0.1905) -> (-3.171, -12.8587)
  line L1 (3.171, -12.8587) -> (3.8052, -0.1905)
  circle A3 centre (0, -12.7) radius 1.5
  dimension "d1" = 4.7244
  dimension "d2" = 7.62
  dimension "d3" = 6.35
  dimension "d4" = 12.7
  dimension "d5" = 3
  constraint coincident A0.centre A1.centre
  constraint concentric A0 A1
  constraint coincident A1 L0.start
  constraint coincident A2 L0.end
  constraint tangent A2 L0
  constraint coincident A2 L1.start
  constraint coincident A1 L1.end
  constraint tangent A1 L1
  constraint tangent A1 L0
  constraint vertical A0.centre A2.centre
  constraint tangent A2 L1
  constraint concentric A2 A3
  measures "d1" diameter of A0
  measures "d2" diameter of A1
  measures "d3" diameter of A2
  measures "d4" vertical distance of A0.centre A2.centre
  measures "d5" diameter of A3
extrude "Extrude1" add sketch "Sketch1" along normal blind 2.54
equation "d1 = ( 0.093 * 2 ) * 1 in"

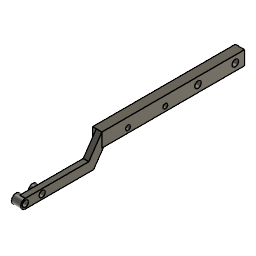
design "Right Cross Beam"
Autodesk Fusion 360 part; units mm, degrees
sketch "Sketch1" plane through (0, 0, 0) normal (1, 0, 0) x (0, 1, 0)
  circle A0 centre (0, 0) radius 2.1971
  circle A1 centre (25.4, 0) radius 2.1971
  line L0 (10.16, 2.54) -> (15.24, 2.54)
  line L1 (15.24, 2.54) -> (15.24, -2.54)
  line L2 (15.24, -2.54) -> (10.16, -2.54)
  line L3 (10.16, -2.54) -> (10.16, 2.54)
  line L4 (-6.35, 4.7625) -> (31.75, 4.7625)
  line L5 (31.75, 4.7625) -> (31.75, -4.7625)
  line L6 (31.75, -4.7625) -> (-6.35, -4.7625)
  line L7 (-6.35, -4.7625) -> (-6.35, 4.7625)
  dimension "d1" = 25.4
  dimension "d2" = 4.3942
  dimension "d3" = 4.3942
  dimension "d4" = 5.08
  dimension "d5" = 5.08
  dimension "d6" = 2.54
  dimension "d7" = 10.16
  dimension "d8" = 9.525
  dimension "d9" = 38.1
  dimension "d10" = 4.7625
  dimension "d11" = 6.35
  constraint horizontal A0.centre A1.centre
  constraint horizontal L0
  constraint vertical L1
  constraint horizontal L2
  constraint vertical L3
  constraint coincident A0.centre origin
  constraint horizontal L4
  constraint vertical L5
  constraint horizontal L6
  constraint vertical L7
  measures "d1" distance of A0.centre A1.centre
  measures "d2" diameter of A0
  measures "d3" diameter of A1
  measures "d4" distance of L0.start L0.end
  measures "d5" distance of L0.start L2.end
  measures "d6" distance of A0.centre L0
  measures "d7" horizontal distance of A0.centre L2.end
  measures "d8" distance of L4.start L6.end
  measures "d9" distance of L4.start L4.end
  measures "d10" distance of A0.centre L4
  measures "d11" distance of A0.centre L7
extrude "Extrude1" add sketch "Sketch1" along normal blind 2.54 makes body 1
sketch "Sketch2" plane through (2.54, 0, 0) normal (1, 0, 0) x (0, 1, 0)
  line L0 (15.24, -2.54) -> (10.16, -2.54)
  line L1 (10.16, -2.54) -> (10.16, 2.54)
  line L2 (10.16, 2.54) -> (15.24, 2.54)
  line L3 (15.24, 2.54) -> (15.24, -2.54)
  circle A0 centre (0, 0) radius 2.1971
  circle A1 centre (25.4, 0) radius 2.1971
  line L4 (-6.35, -4.7625) -> (31.75, -4.7625)
  line L5 (31.75, -4.7625) -> (31.75, 4.7625)
  line L6 (31.75, 4.7625) -> (-6.35, 4.7625)
  line L7 (-6.35, 4.7625) -> (-6.35, -4.7625)
  line L8 (31.75, 4.7625) -> (-6.35, 4.7625)
  line L9 (-6.35, 4.7625) -> (-6.35, -4.7625)
  line L10 (-6.35, -4.7625) -> (31.75, -4.7625)
  line L11 (31.75, -4.7625) -> (31.75, 4.7625)
  circle A2 centre (0, 0) radius 2.1971
  circle A3 centre (25.4, 0) radius 2.1971
  dimension "d14" = 4.3942
  dimension "d15" = 4.3942
  constraint horizontal L8
  constraint vertical L9
  constraint horizontal L10
  constraint vertical L11
  constraint coincident L4.start L7.end
  constraint coincident L5.end L6.start
  constraint concentric A0 A2
  constraint concentric A1 A3
  measures "d14" diameter of A2
  measures "d15" diameter of A3
extrude "Extrude2" add sketch "Sketch2" along normal blind 3.81 contours L0 L1 L2 L3 | L4 L5 L6 L7 L8 L9 L10 L11 bodies 1
sketch "Sketch3" plane through (0, -6.35, 0) normal (0, -1, 0) x (1, 0, 0)
  line L0 (0, 4.7625) -> (0, -4.7625)
  line L1 (0, -4.7625) -> (6.35, -4.7625)
  line L2 (6.35, -4.7625) -> (6.35, 4.7625)
  line L3 (6.35, 4.7625) -> (0, 4.7625)
  line L4 (0, 4.7625) -> (6.35, 4.7625)
  line L5 (6.35, 4.7625) -> (6.35, -4.7625)
  line L6 (6.35, -4.7625) -> (0, -4.7625)
  line L7 (0, -4.7625) -> (0, 4.7625)
  constraint horizontal L4
  constraint vertical L5
  constraint horizontal L6
  constraint vertical L7
  constraint coincident L1.end L2.start
  constraint coincident L0.start L3.end
extrude "Extrude3" add sketch "Sketch3" along normal blind 127 bodies 1
sketch "Sketch4" plane through (6.35, 0, 0) normal (1, 0, 0) x (0, 1, 0)
  circle A0 centre (0, 0) radius 2.1971
  circle A1 centre (25.4, 0) radius 2.1971
  line L0 (31.75, -4.7625) -> (31.75, 4.7625)
  line L1 (31.75, 4.7625) -> (-133.35, 4.7625)
  line L2 (-133.35, 4.7625) -> (-133.35, -4.7625)
  line L3 (-133.35, -4.7625) -> (31.75, -4.7625)
  circle A2 centre (-22.225, -1.5875) radius 1.6
  circle A3 centre (-47.625, -1.5875) radius 1.6
  dimension "d20" = 3.2
  dimension "d21" = 3.2
  dimension "d24" = 6.35
  dimension "d25" = 22.225
  dimension "d48" = 25.4
  constraint horizontal A2.centre A3.centre
  measures "d20" diameter of A2
  measures "d21" diameter of A3
  measures "d24" distance of L1 A2.centre
  measures "d25" horizontal distance of A0.centre A2.centre
  measures "d48" distance of A2.centre A3.centre
extrude "Extrude4" cut sketch "Sketch4" against normal blind 6.35 contours A2 | A3 bodies 1
sketch "Sketch5" plane through (0, -133.35, 0) normal (0, -1, 0) x (1, 0, 0)
  line L0 (0, -4.7625) -> (6.35, -4.7625)
  line L1 (6.35, -4.7625) -> (6.35, 4.7625)
  line L2 (6.35, 4.7625) -> (0, 4.7625)
  line L3 (0, 4.7625) -> (0, -4.7625)
  line L4 (0, -4.7625) -> (6.35, -4.7625)
  line L5 (6.35, -4.7625) -> (6.35, 1.5875)
  line L6 (6.35, 1.5875) -> (0, 1.5875)
  line L7 (0, 1.5875) -> (0, -4.7625)
  dimension "d29" = 6.35
  constraint horizontal L4
  constraint vertical L5
  constraint horizontal L6
  constraint vertical L7
  constraint coincident L1 L5.end
  constraint coincident L0.start L3.end
  measures "d29" distance of L0.end L5.end
extrude "Extrude5" cut sketch "Sketch5" against normal blind 67.945 contours L1 L2 L3 L6 bodies 1
sketch "Sketch6" plane through (0, 0, 0) normal (-1, 0, 0) x (0, -1, 0)
  line L0 (65.405, 1.5875) -> (65.405, 4.7625)
  line L1 (65.405, 4.7625) -> (-31.75, 4.7625)
  line L2 (-31.75, 4.7625) -> (-31.75, -4.7625)
  line L3 (-31.75, -4.7625) -> (133.35, -4.7625)
  line L4 (133.35, -4.7625) -> (133.35, 1.5875)
  line L5 (133.35, 1.5875) -> (65.405, 1.5875)
  circle A0 centre (47.625, -1.5875) radius 1.6
  circle A1 centre (22.225, -1.5875) radius 1.6
  circle A2 centre (0, 0) radius 2.1971
  circle A3 centre (-25.4, 0) radius 2.1971
  line L6 (-10.16, -2.54) -> (-15.24, -2.54)
  line L7 (-15.24, -2.54) -> (-15.24, 2.54)
  line L8 (-15.24, 2.54) -> (-10.16, 2.54)
  line L9 (-10.16, 2.54) -> (-10.16, -2.54)
  circle A4 centre (117.475, -1.5875) radius 2.1
  dimension "d32" = 4.2
  dimension "d33" = 15.875
  dimension "d34" = 3.175
  measures "d32" diameter of A4
  measures "d33" distance of L4 A4.centre
  measures "d34" distance of L3 A4.centre
extrude "Extrude6" cut sketch "Sketch6" against normal blind 6.35 contours A4 bodies 1
sketch "Sketch7" plane through (6.35, 0, 0) normal (1, 0, 0) x (0, 1, 0)
  circle A0 centre (-117.475, -1.5875) radius 2.1
  line L0 (-65.405, 4.7625) -> (-65.405, 1.5875)
  line L1 (-65.405, 1.5875) -> (-133.35, 1.5875)
  line L2 (-133.35, 1.5875) -> (-133.35, -4.7625)
  line L3 (-133.35, -4.7625) -> (31.75, -4.7625)
  line L4 (31.75, -4.7625) -> (31.75, 4.7625)
  line L5 (31.75, 4.7625) -> (-65.405, 4.7625)
  circle A1 centre (25.4, 0) radius 2.1971
  circle A2 centre (0, 0) radius 2.1971
  circle A3 centre (-22.225, -1.5875) radius 1.6
  circle A4 centre (-47.625, -1.5875) radius 1.6
  circle A5 centre (-117.475, -11.4427) radius 2.1
  circle A6 centre (-117.475, -11.4427) radius 3.175
  circle A7 centre (-106.045, -11.4427) radius 2.1
  circle A8 centre (-106.045, -11.4427) radius 3.175
  line L6 (-117.475, -8.2677) -> (-106.045, -8.2677)
  line L7 (-117.475, -14.6177) -> (-106.045, -14.6177)
  line L8 (-65.405, 4.7625) -> (-65.405, -4.7625)
  line L9 (-106.045, -14.6177) -> (-70.9402, -14.6177)
  line L10 (-70.9402, -14.6177) -> (-65.405, -6.5046)
  line L11 (-106.045, -8.2677) -> (-74.295, -8.2677)
  line L12 (-74.295, -8.2677) -> (-65.405, 4.7625)
  line L13 (-65.405, -6.5046) -> (-65.405, -4.7625)
  line L14 (-65.405, -6.5046) -> (-64.2164, -4.7625)
  dimension "d37" = 9.8552
  dimension "d38" = 6.35
  dimension "d43" = 4.2
  dimension "d44" = 6.35
  dimension "d45" = 11.43
  dimension "d49" = 31.75
  dimension "d50" = 6.35
  constraint equal A0 A5
  constraint vertical A0.centre A5.centre
  constraint concentric A5 A6
  constraint concentric A7 A8
  constraint horizontal A5.centre A7.centre
  constraint coincident A6 L6.start
  constraint coincident A8 L6.end
  constraint parallel L3 L6
  constraint coincident A6 L7.start
  constraint coincident A8 L7.end
  constraint coincident L3 L8.end
  constraint horizontal L7
  constraint tangent A6 L7
  constraint tangent A6 L6
  constraint vertical L8.end L0.start
  constraint tangent A8 L9
  constraint parallel L3 L9
  constraint coincident L8 L10.end
  constraint tangent A8 L11
  constraint parallel L3 L11
  constraint coincident L0.start L5.end
  constraint vertical L0.start L5.end
  constraint parallel L10 L12
  constraint coincident L3 L14.end
  constraint parallel L10 L14
  measures "d37" vertical distance of A0.centre A5.centre
  measures "d38" diameter of A6
  measures "d43" diameter of A7
  measures "d44" diameter of A8
  measures "d45" distance of A5.centre A7.centre
  measures "d49" horizontal distance of A7.centre L11.end
  measures "d50" distance of L10 L12
extrude "Extrude7" cut sketch "Sketch7" against normal blind 6.35 contours L0 L1 L8 L12 | L1 L3 L8 L12 | L1 L2 L3 L12 | A1 | A2 | A3 | A4 bodies 1
extrude "Extrude8" add sketch "Sketch7" against normal blind 3.81 separate body contours L0 L1 L8 L12 | L1 L3 L8 L12 | L3 A8 L9 L10 L11 L12 L13 | L3 L13 L14 | A8 | A6 A8 L6 L7 | A6 makes body 2
extrude "Extrude9" add sketch "Sketch7" against normal blind 6.35 contours A8 | A6 bodies 2
equation "d7 = 0.5 in - ( 0.2 / 2 ) * 1 in"
equation "d10 = ( 0.375 / 2 ) * 1 in"
equation "d11 = ( ( 1.5 - 1 ) / 2 ) * 1 in"
equation "d37 = 0.263 in + 0.125 in"

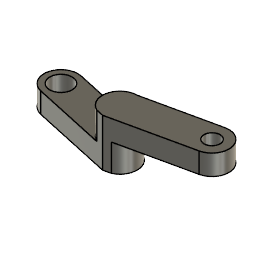
design "Left Control Arm"
Autodesk Fusion 360 part; units mm, degrees
sketch "Sketch1" plane through (0, 0, 0) normal (0, 0, 1) x (1, 0, 0)
  circle A0 centre (0, 0) radius 2.0955
  circle A1 centre (28.2448, 0) radius 1.5
  circle A2 centre (0, 0) radius 3.175
  circle A3 centre (28.2448, 0) radius 3.175
  line L0 (27.5642, 3.1012) -> (14.1224, 0.1511)
  line L1 (14.1224, 0.1511) -> (0.6806, 3.1012)
  line L2 (28.9254, -3.1012) -> (14.1224, -6.35)
  line L3 (14.1224, -6.35) -> (-0.6806, -3.1012)
  dimension "d1" = 3
  dimension "d2" = 4.191
  dimension "d3" = 28.2448
  dimension "d4" = 6.35
  dimension "d5" = 6.35
  dimension "d14" = 6.35
  constraint coincident A0.centre A2.centre
  constraint concentric A1 A3
  constraint horizontal A0.centre A1.centre
  constraint coincident A3 L0.start
  constraint coincident A2 L1.end
  constraint coincident A3 L2.start
  constraint parallel L0 L2
  constraint coincident A2 L3.end
  constraint tangent A2 L3
  constraint tangent A2 L1
  constraint tangent A3 L0
  constraint tangent A3 L2
  constraint parallel L1 L3
  constraint vertical L0.end L2.end
  measures "d1" diameter of A1
  measures "d2" diameter of A0
  measures "d3" distance of A0.centre A1.centre
  measures "d4" diameter of A3
  measures "d5" diameter of A2
  measures "d14" vertical distance of A1.centre L2.end
extrude "Extrude1" add sketch "Sketch1" along normal blind 3.81
sketch "Sketch3" plane through (0, 0, 0) normal (0, 0, -1) x (1, 0, 0)
  circle A0 centre (0, 0) radius 2.0955
  circle A1 centre (28.2448, 0) radius 1.5
  line L0 (0.6806, -3.1012) -> (14.1224, -0.1511)
  line L1 (14.1224, -0.1511) -> (27.5642, -3.1012)
  arc A2 (27.5642, -3.1012) -> (28.9254, 3.1012) centre (28.2448, 0) ccw
  line L2 (28.9254, 3.1012) -> (14.1224, 6.35)
  line L3 (14.1224, 6.35) -> (-0.6806, 3.1012)
  arc A3 (-0.6806, 3.1012) -> (0.6806, -3.1012) centre (0, 0) ccw
  line L4 (14.1224, 6.35) -> (14.1224, -0.1511)
  circle A4 centre (0, 0) radius 3.175
  line L5 (14.1224, 6.35) -> (-0.6806, 3.1012)
  line L6 (14.1224, -0.1511) -> (0.6806, -3.1012)
  circle A5 centre (14.1224, 3.0994) radius 3.2506
  constraint coincident L2.end L3.start
  constraint coincident L0.end L1.start
  constraint coincident A0.centre A3.centre
  constraint coincident L3.end A3.start
  constraint tangent A4 L5
  constraint coincident L0.start A3.end
  constraint midpoint L4 A5.centre
  constraint coincident L2.end A5
extrude "Extrude3" add sketch "Sketch3" along normal blind 1.27 and the other way blind 1.905 contours L3 L4 L5 A5 | L2 L4 A5
sketch "Sketch2" plane through (0, 0, 0) normal (0, 0, -1) x (1, 0, 0)
  circle A0 centre (28.2448, 0) radius 1.5
  arc A1 (27.5642, -3.1012) -> (28.9254, 3.1012) centre (28.2448, 0) ccw
  circle A2 centre (0, 0) radius 2.0955
  circle A3 centre (0, 0) radius 3.175
  line L0 (14.1224, -0.1511) -> (27.5642, -3.1012)
  line L1 (28.9254, 3.1012) -> (15.4836, 6.0513)
  circle A4 centre (0, 0) radius 2.0955
  line L2 (0.6806, -3.1012) -> (14.1224, -0.1511)
  line L3 (12.7612, 6.0513) -> (-0.6806, 3.1012)
  arc A5 (-0.6806, 3.1012) -> (0.6806, -3.1012) centre (0, 0) ccw
  arc A6 (14.1224, -0.1511) -> (15.4836, 6.0513) centre (14.1224, 3.0994) ccw
  arc A7 (12.7612, 6.0513) -> (14.1224, -0.1511) centre (14.1224, 3.0994) ccw
  dimension "d8" = 4.191
  dimension "d9" = 6.35
  measures "d8" diameter of A2
  measures "d9" diameter of A3
extrude "Extrude2" cut sketch "Sketch2" against normal blind 5.588 contours A3 L2 L3 A7 | A3 A5
sketch "Sketch4" plane through (0, 0, -1.27) normal (0, 0, -1) x (1, 0, 0)
  arc A0 (12.7612, 6.0513) -> (15.4836, 6.0513) centre (14.1224, 3.0994) ccw
  line L0 (15.4836, 6.0513) -> (14.1224, 6.35)
  line L1 (14.1224, 6.35) -> (12.7612, 6.0513)
  circle A1 centre (0, 0) radius 2.0955
  circle A2 centre (0, 0) radius 3.175
  line L2 (13.4418, 6.2006) -> (-0.6806, 3.1012)
  line L3 (0.6806, -3.1012) -> (14.1224, -0.1511)
  dimension "d19" = 4.191
  dimension "d20" = 6.35
  dimension "d21" = 13.4418
  constraint coincident A1.centre A2.centre
  constraint concentric A1 A2
  constraint midpoint L1 L2.start
  constraint coincident A2 L2.end
  constraint tangent A2 L2
  constraint coincident A2 L3.start
  constraint midpoint A0 L3.end
  measures "d19" diameter of A1
  measures "d20" diameter of A2
  measures "d21" horizontal distance of L3.start L3.end
extrude "Extrude4" add sketch "Sketch4" along normal blind 3.81
equation "d3 = 1.235 in - 0.123 in"

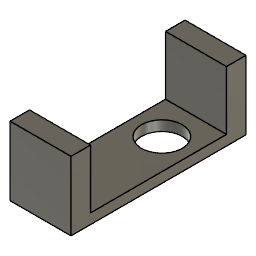
design "Servo Mounting"
Autodesk Fusion 360 part; units mm, degrees
sketch "Sketch1" plane through (0, 0, 0) normal (0, 0, 1) x (1, 0, 0)
  line L0 (0, 0) -> (18.9992, 0)
  line L1 (18.9992, 0) -> (18.9992, 54.5084)
  line L2 (18.9992, 54.5084) -> (0, 54.5084)
  line L3 (0, 54.5084) -> (0, 0)
  line L4 (9.4996, 54.5084) -> (9.4996, 37.7952)
  circle A0 centre (9.4996, 37.7952) radius 6.35
  dimension "d1" = 18.9992
  dimension "d2" = 54.5084
  dimension "d3" = 16.7132
  dimension "d4" = 12.7
  constraint horizontal L0
  constraint vertical L1
  constraint horizontal L2
  constraint vertical L3
  constraint coincident L0.start L3.end
  constraint midpoint L2 L4.start
  constraint perpendicular L2 L4
  constraint coincident L4.end A0.centre
  measures "d1" distance of L0.start L0.end
  measures "d2" distance of L0.start L2.end
  measures "d3" distance of L4.start L4.end
  measures "d4" diameter of A0
extrude "Extrude1" add sketch "Sketch1" along normal blind 3.175
sketch "Sketch2" plane through (0, 0, 3.175) normal (0, 0, 1) x (-1, 0, 0)
  circle A0 centre (-9.4996, -37.7952) radius 6.35
  line L0 (0, -54.5084) -> (0, 0)
  line L1 (0, 0) -> (-18.9992, 0)
  line L2 (-18.9992, 0) -> (-18.9992, -54.5084)
  line L3 (-18.9992, -54.5084) -> (0, -54.5084)
  line L4 (0, -54.5084) -> (-19.6618, -54.5084)
  line L5 (-19.6618, -48.4124) -> (0, -48.4124)
  line L6 (0, -48.4124) -> (0, -54.5084)
  line L7 (0, 0) -> (-18.9992, 0)
  line L8 (-18.9992, 0) -> (-18.9992, -6.096)
  line L9 (-18.9992, -6.096) -> (0, -6.096)
  line L10 (0, -6.096) -> (0, 0)
  line L11 (0, -54.5084) -> (-18.9992, -54.5084)
  line L12 (-18.9992, -54.5084) -> (-18.9992, -48.4124)
  line L13 (-18.9992, -48.4124) -> (0, -48.4124)
  line L14 (0, -48.4124) -> (0, -54.5084)
  dimension "d7" = 6.096
  dimension "d8" = 6.096
  constraint horizontal L4
  constraint horizontal L5
  constraint vertical L6
  constraint coincident L0.start L3.end
  constraint horizontal L7
  constraint vertical L8
  constraint horizontal L9
  constraint vertical L10
  constraint coincident L0.end L1.start
  constraint horizontal L11
  constraint vertical L12
  constraint horizontal L13
  constraint vertical L14
  constraint coincident L5 L12.end
  constraint coincident L2 L12.end
  measures "d7" distance of L0.start L5.end
  measures "d8" distance of L0.end L9.end
extrude "Extrude2" add sketch "Sketch2" along normal blind 18.288 contours L0 L2 L3 L4 L5 L6 L11 L12 L13 L14 | L0 L1 L2 L7 L8 L9 L10

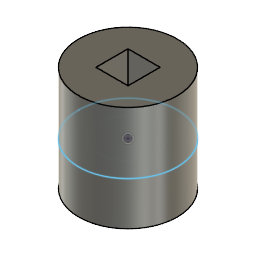
design "Servo Adapter"
Autodesk Fusion 360 part; units mm, degrees
sketch "Sketch1" plane through (0, 0, 0) normal (0, 0, 1) x (1, 0, 0)
  circle A0 centre (0, 0) radius 2.8575
  circle A1 centre (0, 0) radius 5.08
  dimension "d1" = 5.715
  dimension "d2" = 10.16
  constraint coincident A0.centre A1.centre
  constraint concentric A0 A1
  measures "d1" diameter of A0
  measures "d2" diameter of A1
extrude "Extrude1" add sketch "Sketch1" along normal blind 4.4958
sketch "Sketch2" plane through (0, 0, 4.4958) normal (0, 0, 1) x (-1, 0, 0)
  circle A0 centre (0, 0) radius 2.8575
  circle A1 centre (0, 0) radius 5.08
  circle A2 centre (0, 0) radius 5.08
  constraint coincident A0.centre A1.centre
sketch "Sketch3" plane through (0, 0, 4.4958) normal (0, 0, 1) x (-1, 0, 0)
  line L0 (-1.651, -1.651) -> (1.651, -1.651)
  line L1 (1.651, -1.651) -> (1.651, 1.651)
  line L2 (1.651, 1.651) -> (-1.651, 1.651)
  line L3 (-1.651, 1.651) -> (-1.651, -1.651)
  line L4 (-1.651, -1.651) -> (1.651, 1.651) construction
  line L5 (1.651, -1.651) -> (-1.651, 1.651) construction
  circle A0 centre (0, 0) radius 5.08
  dimension "d5" = 3.302
  dimension "d6" = 3.302
  constraint horizontal L0
  constraint perpendicular L0 L1
  constraint parallel L0 L2
  constraint parallel L1 L3
  constraint coincident L4 A0.centre
  constraint coincident L5 A0.centre
  constraint coincident A0.centre origin
  measures "d5" distance of L1.end L2.end
  measures "d6" distance of L0.end L1.end
extrude "Extrude2" add sketch "Sketch3" along normal blind 6.35

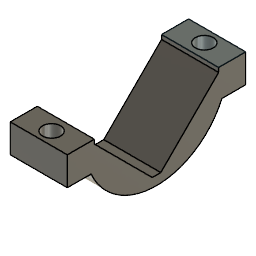
design "Drive Motor Mount Base"
Autodesk Fusion 360 part; units mm, degrees
ref_plane "WorkPlane1" through (0, 0, 0) normal (1, 0, 0) x (0, 1, 0)
sketch "Sketch3" plane through (0, 0, 0) normal (1, 0, 0) x (0, 1, 0)
  line L0 (-15.875, 0) -> (15.875, 0)
  line L1 (15.875, 0) -> (15.875, -12.7)
  line L2 (15.875, -12.7) -> (-15.875, -12.7)
  line L3 (-15.875, -12.7) -> (-15.875, 0)
  line L4 (-11.049, 0) -> (-11.049, -0.762)
  line L5 (-11.049, -0.762) -> (-0.762, -11.049)
  line L6 (-0.762, -11.049) -> (0.762, -11.049)
  line L7 (0.762, -11.049) -> (11.049, -0.762)
  line L8 (11.049, -0.762) -> (11.049, 0)
  dimension "d12" = 31.75
  dimension "d13" = 12.7
  dimension "d14" = 0.762
  dimension "d15" = 4.826
  dimension "d16" = 4.826
  dimension "d17" = 1.524
  constraint horizontal L0
  constraint vertical L1
  constraint horizontal L2
  constraint vertical L3
  constraint coincident L0 L4.start
  constraint perpendicular L0 L4
  constraint horizontal L6
  constraint coincident L0 L8.end
  constraint perpendicular L0 L8
  constraint equal L4 L8
  constraint equal L5 L7
  constraint perpendicular L5 L7
  constraint midpoint origin L0
  measures "d12" distance of L1.end L2.end
  measures "d13" distance of L0.start L2.end
  measures "d14" distance of L4.start L4.end
  measures "d15" distance of L0.start L4.start
  measures "d16" distance of L0.end L8.end
  measures "d17" distance of L5.end L6.end
extrude "Extrude2" add sketch "Sketch3" along normal blind 10.16 contours L0 L1 L2 L3 L4 L5 L6 L7 L8